MOD-GRID Skeletool Holder (Autodesk Fusion 360 design; units mm, degrees)
part number: 2026-10-25-08-48-38-444
Autodesk Fusion 360 part; units mm, degrees
ref_plane "WorkPlane52" through (-15.8, 0, 0) normal (1, 0, 0) x (0, 1, 0)
sketch "Tool section" plane through (-15.8, 0, 0) normal (1, 0, 0) x (0, 0, -1)
  arc A0 (-6, 14.25) -> (-7.5, 15.75) centre (-7.5, 14.25) ccw
  arc A1 (-17.7, 15.75) -> (-19.2, 14.25) centre (-17.7, 14.25) ccw
  arc A2 (-19.2, -14.25) -> (-17.7, -15.75) centre (-17.7, -14.25) ccw
  arc A3 (-7.5, -15.75) -> (-6, -14.25) centre (-7.5, -14.25) ccw
  line L0 (-6, 14.25) -> (-6, -14.25)
  line L1 (-7.5, 15.75) -> (-17.7, 15.75)
  line L2 (-19.2, 14.25) -> (-19.2, -14.25)
  line L3 (-7.5, -15.75) -> (-17.7, -15.75)
extrude "Extrude82" add sketch "Tool section" along normal blind 85.8 makes body 1
ref_plane "WorkPlane53" through (70, 0, 0) normal (1, 0, 0) x (0, 1, 0)
sketch "Tool end section" plane through (70, 0, 0) normal (1, 0, 0) x (0, 0, -1)
  arc A0 (-6, 12) -> (-7.5, 13.5) centre (-7.5, 12) ccw
  arc A1 (-12.5, 13.5) -> (-14, 12) centre (-12.5, 12) ccw
  arc A2 (-14, -12) -> (-12.5, -13.5) centre (-12.5, -12) ccw
  arc A3 (-7.5, -13.5) -> (-6, -12) centre (-7.5, -12) ccw
  line L0 (-6, 12) -> (-6, -12)
  line L1 (-7.5, 13.5) -> (-12.5, 13.5)
  line L2 (-14, 12) -> (-14, -12)
  line L3 (-7.5, -13.5) -> (-12.5, -13.5)
extrude "Extrude83" add sketch "Tool end section" along normal blind 15.8 bodies 1
ref_plane "WorkPlane54" through (7, 0, 0) normal (1, 0, 0) x (0, 1, 0)
sketch "Band A body" plane through (7, 0, 0) normal (1, 0, 0) x (0, 0, -1)
  line L0 (0, -23.45) -> (-22.8627, -23.45)
  line L1 (-22.8627, -23.45) -> (-22.8627, 23.45)
  line L2 (-22.8627, 23.45) -> (0, 23.45)
  line L3 (0, 23.45) -> (0, -23.45)
extrude "Extrude84" add sketch "Band A body" along normal blind 7 and the other way blind 7 separate body makes body 2
fillet "Fillet19" radius 1.5 4 edges at (7, 23.45, 0) (7, -23.45, 0) (7, -23.45, 22.8627) (7, 23.45, 22.8627) on bodies 2
sketch "Band A cavity" plane through (7, 0, 0) normal (1, 0, 0) x (0, 0, -1)
  arc A0 (-6, 16.15) -> (-6.3, 16.45) centre (-6.3, 16.15) ccw
  arc A1 (-20.8299, 15.4172) -> (-20.2642, 15.4172) centre (-20.5471, 15.7) ccw
  line L0 (-6.3, 16.45) -> (-19.2314, 16.45)
  line L1 (-19.2314, 16.45) -> (-20.2642, 15.4172)
  line L2 (-20.8299, 15.4172) -> (-21.8627, 16.45)
  line L3 (-21.8627, 16.45) -> (-24.8627, 16.45)
  arc A2 (-6.3, -16.45) -> (-6, -16.15) centre (-6.3, -16.15) ccw
  arc A3 (-20.2642, -15.4172) -> (-20.8299, -15.4172) centre (-20.5471, -15.7) ccw
  line L4 (-6.3, -16.45) -> (-19.2314, -16.45)
  line L5 (-19.2314, -16.45) -> (-20.2642, -15.4172)
  line L6 (-20.8299, -15.4172) -> (-21.8627, -16.45)
  line L7 (-21.8627, -16.45) -> (-24.8627, -16.45)
  line L8 (-6, -16.15) -> (-6, 16.15)
  line L9 (-24.8627, -16.45) -> (-24.8627, 16.45)
extrude "Extrude85" cut sketch "Band A cavity" along normal blind 14 and the other way blind 14 bodies 2
sketch "Band A relief" plane through (7, 0, 0) normal (1, 0, 0) x (0, 0, -1)
  arc A0 (-3.387, 15.0897) -> (-6.3, 19.25) centre (-6.3, 16.15) ccw
  arc A1 (-2.2593, 14.6793) -> (-6.3, 20.45) centre (-6.3, 16.15) ccw
  line L0 (-6.3, 19.25) -> (-10.3, 18.45)
  line L1 (-10.3, 18.45) -> (-24.8627, 18.45)
  line L2 (-24.8627, 18.45) -> (-24.8627, 20.45)
  line L3 (-24.8627, 20.45) -> (-6.3, 20.45)
  line L4 (-2.2593, 14.6793) -> (-3.387, 15.0897)
  circle A2 centre (-2.8231, 14.8845) radius 0.6
  arc A3 (-6.3, -19.25) -> (-3.387, -15.0897) centre (-6.3, -16.15) ccw
  arc A4 (-6.3, -20.45) -> (-2.2593, -14.6793) centre (-6.3, -16.15) ccw
  line L5 (-6.3, -19.25) -> (-10.3, -18.45)
  line L6 (-10.3, -18.45) -> (-24.8627, -18.45)
  line L7 (-24.8627, -18.45) -> (-24.8627, -20.45)
  line L8 (-24.8627, -20.45) -> (-6.3, -20.45)
  line L9 (-2.2593, -14.6793) -> (-3.387, -15.0897)
  circle A5 centre (-2.8231, -14.8845) radius 0.6
extrude "Extrude86" cut sketch "Band A relief" along normal blind 14 and the other way blind 14 bodies 2
chamfer "Chamfer19" distance 0.5 angle 45 16 edges at (0, 21.2, 22.8627) (0, 23.0107, 22.4234) (0, 23.45, 11.4314) (0, 23.0107, 0.4393) (0, 0, 0) (0, -23.0107, 0.4393) (0, -23.45, 11.4314) (0, -23.0107, 22.4234) (0, -21.2, 22.8627) (0, -17.45, 22.8627) (0, -16.45, 12.7657) (0, -16.3621, 6.0879) (0, 0, 6) (0, 16.3621, 6.0879) (0, 16.45, 12.7657) (0, 17.45, 22.8627) tangent chain off on bodies 2
ref_plane "WorkPlane55" through (0, 0, 0) normal (1, 0, 0) x (0, 1, 0)
sketch "Band A legs" plane through (0, 0, 0) normal (1, 0, 0) x (0, 0, -1)
  line L0 (-0.5, -13.45) -> (4.64, -13.45)
  line L1 (4.64, -13.45) -> (4.64, -13.93)
  line L2 (4.64, -13.93) -> (3.4, -15.19)
  line L3 (3.4, -15.19) -> (3.1, -14.32)
  line L4 (3.1, -14.32) -> (-0.5, -14.32)
  line L5 (-0.5, -14.32) -> (-0.5, -13.45)
  line L6 (-0.5, -10.55) -> (4.64, -10.55)
  line L7 (4.64, -10.55) -> (4.64, -10.07)
  line L8 (4.64, -10.07) -> (3.4, -8.81)
  line L9 (3.4, -8.81) -> (3.1, -9.68)
  line L10 (3.1, -9.68) -> (-0.5, -9.68)
  line L11 (-0.5, -9.68) -> (-0.5, -10.55)
  line L12 (-0.5, 10.55) -> (4.64, 10.55)
  line L13 (4.64, 10.55) -> (4.64, 10.07)
  line L14 (4.64, 10.07) -> (3.4, 8.81)
  line L15 (3.4, 8.81) -> (3.1, 9.68)
  line L16 (3.1, 9.68) -> (-0.5, 9.68)
  line L17 (-0.5, 9.68) -> (-0.5, 10.55)
  line L18 (-0.5, 13.45) -> (4.64, 13.45)
  line L19 (4.64, 13.45) -> (4.64, 13.93)
  line L20 (4.64, 13.93) -> (3.4, 15.19)
  line L21 (3.4, 15.19) -> (3.1, 14.32)
  line L22 (3.1, 14.32) -> (-0.5, 14.32)
  line L23 (-0.5, 14.32) -> (-0.5, 13.45)
extrude "Extrude87" add sketch "Band A legs" along normal blind 4.76 bodies 2
ref_plane "WorkPlane56" through (80.4, 0, 0) normal (1, 0, 0) x (0, 1, 0)
sketch "Pocket body" plane through (80.4, 0, 0) normal (1, 0, 0) x (0, 0, -1)
  line L0 (0, -23.45) -> (-16.07, -23.45)
  line L1 (-16.07, -23.45) -> (-16.07, 23.45)
  line L2 (-16.07, 23.45) -> (0, 23.45)
  line L3 (0, 23.45) -> (0, -23.45)
extrude "Extrude88" add sketch "Pocket body" along normal blind 8.4 and the other way blind 8.4 separate body makes body 3
fillet "Fillet20" radius 1.5 4 edges at (80.4, 23.45, 0) (80.4, -23.45, 0) (80.4, -23.45, 16.07) (80.4, 23.45, 16.07) on bodies 3
ref_plane "WorkPlane57" through (72, 0, 0) normal (1, 0, 0) x (0, 1, 0)
sketch "Pocket cavity" plane through (72, 0, 0) normal (1, 0, 0) x (0, 0, -1)
  arc A0 (-5.83, 13.57) -> (-6.13, 13.87) centre (-6.13, 13.57) ccw
  arc A1 (-14.27, 13.87) -> (-14.57, 13.57) centre (-14.27, 13.57) ccw
  arc A2 (-14.57, -13.57) -> (-14.27, -13.87) centre (-14.27, -13.57) ccw
  arc A3 (-6.13, -13.87) -> (-5.83, -13.57) centre (-6.13, -13.57) ccw
  line L0 (-5.83, 13.57) -> (-5.83, -13.57)
  line L1 (-6.13, 13.87) -> (-14.27, 13.87)
  line L2 (-14.57, 13.57) -> (-14.57, -13.57)
  line L3 (-6.13, -13.87) -> (-14.27, -13.87)
extrude "Extrude89" cut sketch "Pocket cavity" along normal blind 14.3 and the other way blind 14.3 bodies 3
chamfer "Chamfer20" distance 0.5 angle 45 16 edges at (72, 0, 5.83) (72, 13.7821, 5.9179) (72, 13.87, 10.2) (72, 13.7821, 14.4821) (72, 0, 14.57) (72, -13.7821, 14.4821) (72, -13.87, 10.2) (72, -13.7821, 5.9179) (72, 23.0107, 15.6307) (72, 0, 16.07) (72, -23.0107, 15.6307) (72, -23.45, 8.035) (72, -23.0107, 0.4393) (72, 0, 0) (72, 23.0107, 0.4393) (72, 23.45, 8.035) tangent chain off on bodies 3
ref_plane "WorkPlane58" through (72, 0, 0) normal (1, 0, 0) x (0, 1, 0)
sketch "Tip Pocket legs" plane through (72, 0, 0) normal (1, 0, 0) x (0, 0, -1)
  line L0 (-0.5, -13.45) -> (4.64, -13.45)
  line L1 (4.64, -13.45) -> (4.64, -13.93)
  line L2 (4.64, -13.93) -> (3.4, -15.19)
  line L3 (3.4, -15.19) -> (3.1, -14.32)
  line L4 (3.1, -14.32) -> (-0.5, -14.32)
  line L5 (-0.5, -14.32) -> (-0.5, -13.45)
  line L6 (-0.5, -10.55) -> (4.64, -10.55)
  line L7 (4.64, -10.55) -> (4.64, -10.07)
  line L8 (4.64, -10.07) -> (3.4, -8.81)
  line L9 (3.4, -8.81) -> (3.1, -9.68)
  line L10 (3.1, -9.68) -> (-0.5, -9.68)
  line L11 (-0.5, -9.68) -> (-0.5, -10.55)
  line L12 (-0.5, 10.55) -> (4.64, 10.55)
  line L13 (4.64, 10.55) -> (4.64, 10.07)
  line L14 (4.64, 10.07) -> (3.4, 8.81)
  line L15 (3.4, 8.81) -> (3.1, 9.68)
  line L16 (3.1, 9.68) -> (-0.5, 9.68)
  line L17 (-0.5, 9.68) -> (-0.5, 10.55)
  line L18 (-0.5, 13.45) -> (4.64, 13.45)
  line L19 (4.64, 13.45) -> (4.64, 13.93)
  line L20 (4.64, 13.93) -> (3.4, 15.19)
  line L21 (3.4, 15.19) -> (3.1, 14.32)
  line L22 (3.1, 14.32) -> (-0.5, 14.32)
  line L23 (-0.5, 14.32) -> (-0.5, 13.45)
extrude "Extrude90" add sketch "Tip Pocket legs" along normal blind 4.76 bodies 3
equation "tool_w = 31.50 mm" comment "OFFICIAL LEATHERMAN SPEC, closed (1.24 in). Across the handles - the direction that lies flat on the plate. NOT yet caliper-checked on the actual tool."
equation "tool_t = 13.20 mm" comment "OFFICIAL LEATHERMAN SPEC, closed overall thickness (0.52 in). This is the dimension the bands reach over. The multitool.org wiki says 16 mm, which is almost certainly WITH the removable pocket clip fitted - see the notes at the top of this file."
equation "tool_len = 101.60 mm" comment "OFFICIAL LEATHERMAN SPEC, closed length (4.00 in). Only sets where the reference body ends and how far apart the bands can sit."
equation "tool_r = 1.50 mm" comment "ESTIMATE of the cross-section corner radius. Unlike the Skeletool, NOTHING IN THIS DESIGN DEPENDS ON IT: the cavity is squarer than any plausible value and the bead sits entirely ABOVE the tool's top face, so it overhangs the flat rather than grazing the corner. It only shapes the reference body. run() sweeps 0..4 to prove the insensitivity rather than assert it."
equation "cav_clear = 1.40 mm" comment "Clearance on the cavity width (total)"
equation "cav_hw = ( tool_w + cav_clear ) / 2" comment "Cavity half width"
equation "cav_r = 0.30 mm" comment "Cavity bottom corner radius. SQUARER than the tool on purpose: a cavity corner rounder than the tool is what jammed every previous version. Also the arc the relief slot follows."
equation "base_t = 6.00 mm" comment "Base under the tool. It sets how far the slot root sits above the z=0 face (base_t + cav_r - r_out, want >= 1.5); it does NOT set the root web, which is base_t-independent because the cavity floor and the slot rise together."
equation "arm_root = 2.80 mm" comment "Arm thickness AT THE ROOT = 7 extrusions at 0.4. The arm is TAPERED, thick at the base and thinner at the tip, because the bending moment is largest at the root and nearly zero at the bead. A thick root also pushes the relief slot further out, which is what gives the root web its thickness - see root_web()."
equation "arm_tip = 2.00 mm" comment "Arm thickness at the bead = 5 extrusions. Keep every flexure wall an integer multiple of the extrusion width and >= 4 of them: 1.2 mm is 2.86 extrusions, so the slicer lays a gap-fill bond line down the middle of the flexure."
equation "arm_blend = 4.00 mm" comment "Height above the cavity corner over which arm_root blends down to arm_tip. A step here would be a stress riser; blending over several mm keeps the thick material where the moment is and still leaves most of the arm compliant."
equation "relief_w = 1.20 mm" comment "Relief slot width behind the arm"
equation "relief_a0 = -110 deg" comment "Relief slot root angle about the cavity corner centre. Past -90 it tucks under the floor and buys arm length, but it also EATS THE ROOT WEB: past -90 the nearest cavity surface is the floor, not the corner arc, so the web stops being arm_root and starts shrinking fast. -135 left only 0.52 mm, which the bed chamfer then cut to 0.016. run() computes it."
equation "rail_t = 3.00 mm" comment "Outer rail beyond the relief slot. With body_corner_r it sets the top land between slot and fillet: keep that > 2 * first_layer_cham."
equation "bead_clear = 0.10 mm" comment "Gap between the BOTTOM of the bead and the tool's top face when seated. Also the lift play before the bead bites."
equation "lip_over = 0.45 mm" comment "How far each bead reaches inboard of the tool's side face - and therefore the splay each arm takes. This IS the deflection, and deflection sets the bending stress, so it is budgeted against SIG_LIMIT rather than maximised. Thinning an arm to buy more reach is exactly the mistake that produced a 0.016 mm root web on the Skeletool band."
equation "bead_r = lip_over + cav_clear / 2" comment "Bead radius. Half circle tangent to the cavity wall above and below, so the arm's inner face is one continuous curve with no tooth to snap off."
equation "bead_z = base_t + tool_t + bead_clear + bead_r" comment "Bead centre height, placed so the bead's LOWEST point sits bead_clear above the tool's top face. The whole bead is therefore above the top face and overhangs the FLAT, never the corner - which is why tool_r drops out of the design. It also lengthens the arm by a bead radius over the Skeletool's corner-tangent rule, which is worth about 1 MPa."
equation "lip_tip_y = tool_w / 2 - lip_over" comment "Innermost point of the bead"
equation "land_h = 1.00 mm" comment "Band height above the bead"
equation "band_len = 14.0 mm" comment "Band width along the tool = part height when printed. Grip force scales with band length and peak stress does NOT, so length is the one free way to buy retention."
equation "band_hw = cav_hw + arm_root + relief_w + rail_t" comment "Band half width - set by the ROOT thickness, which is the widest part of the arm"
equation "band_h = lip_z0 + 2 * lip_proj + land_h" comment "Band overall height"
equation "band_a_x = 0 mm" comment "Band A bed face"
equation "band_cells = 7" comment "Grid cells between the two bands = 56 mm. Keeps both bands on the straight part of the handle, clear of the plier head at one end and the carabiner at the other."
equation "grid_pitch = 8 mm" comment "MOD-GRID pitch"
equation "band_b_x = band_a_x + band_cells * grid_pitch" comment "Band B bed face"
equation "body_corner_r = 1.50 mm" comment "Rounded outer corners"
equation "first_layer_cham = 0.50 mm" comment "Elephant-foot chamfer on the bed face"
equation "leg_pair_y = 12.0 mm" comment "Leg pairs at +/- this; 24 mm apart = 3 cells"
equation "leg_clear = 0.14 mm" comment "Shrinks the leg LENGTH and SHANK (not the barb). MEASURED: this printer runs 0.07 per wall."
equation "leg_hole_len = 4.90 mm - leg_clear" comment "Leg extent along the print axis"
equation "leg_inner_hw = 1.45 mm" comment "Leg inner face from pair centre -> 2.90 gap"
equation "leg_shank_hw = 2.39 mm - leg_clear / 2" comment "Relaxed shank half-span"
equation "barb_hw = 3.19 mm" comment "Barb peak half-span - NOT reduced, it is meant to squeeze"
equation "barb_z = -3.40 mm" comment "Barb peak depth below the seating face"
equation "catch_z = -3.10 mm" comment "Catch face: 0.10 below the 3.00 plate"
equation "leg_tip_z = -4.64 mm" comment "Leg tip"
equation "leg_tip_hw = 2.00 mm - leg_clear / 2" comment "Tip half-span, sets the ~45 deg lead-in"
equation "tool_r_min = 0.20 mm" comment "The SQUAREST corner the handle could plausibly have. The capture lip is placed so it still clears THIS at seated, which is the recoverable bias: a squarer tool can never be held proud, a rounder one only lifts further before the lip bites."
equation "lip_clear = 0.60 mm" comment "Gap between the lip's underside and the tool's top corner when seated, evaluated at tool_r_min. The arms are UNLOADED when the tool is home, so there is no creep."
equation "lip_tipr = 0.40 mm" comment "Radius on the lip tip = ONE NOZZLE WIDTH. A knife edge will not print. It also confines the only part of the stroke where the contact normal can reach horizontal - see seat_check(); a round bead lets that happen over ~0.5 mm and the Zippo band printed with one held the lighter 2 mm proud."
equation "lip_apex_y = lip_tip_y - 0.4142135624 * lip_tipr" comment "Virtual apex where the two 45 deg faces would meet if the tip were not rounded"
equation "lip_proj = cav_hw - lip_apex_y" comment "How far the apex stands proud of the cavity wall. At 45 deg this is also the RISE of each face, so the lip is 2 * lip_proj tall."
equation "lip_z0 = 1.4142135624 * ( tool_r_min + lip_clear ) + tool_w / 2 + base_t + tool_t - 2 * tool_r_min - cav_hw" comment "Foot of the capture ramp, where the 45 deg underside leaves the cavity wall. Derived, not chosen: the underside is the line y + z = cav_hw + lip_z0, and this is the lowest it can sit while still standing lip_clear off a tool corner of radius tool_r_min."
equation "lip_zt = lip_z0 + lip_proj" comment "Height of the lip tip = where the load is applied to the arm"
equation "tool_overhang = 15.80 mm" comment "How much tool stands proud of Band A's bed face. Frozen at the value the old two-band layout produced - (band_a_x + band_b_x + band_len - tool_len) / 2 with Band B at 7 cells - so that BAND A STILL GRIPS EXACTLY THE SAME PART OF THE HANDLE as the version Rob has printed and likes. Do not \"tidy\" this to zero without re-checking what the band lands on."
equation "tool_x0 = band_a_x - tool_overhang" comment "Tool's near end"
equation "print_bias = 0.07 mm" comment "MEASURED on this printer: a cavity comes out 0.07 per wall UNDER nominal. The pocket is modelled oversize by this so the INTERNAL DIMENSIONS PRINT AT THE NUMBERS ROB ASKED FOR, rather than 0.14 under them."
equation "pocket_id_w = 27.60 mm" comment "Pocket internal WIDTH as it should measure ON THE PRINTED PART. The cut is modelled 2 * print_bias wider than this."
equation "pocket_id_h = 8.60 mm" comment "Pocket internal HEIGHT as it should measure ON THE PRINTED PART."
equation "pocket_cells = 9" comment "Grid cells from Band A to the pocket mouth = 72 mm, which puts the mouth 13.8 mm short of the tool's far end so that much of the tool is captured."
equation "pocket_x0 = band_a_x + pocket_cells * grid_pitch" comment "Pocket MOUTH = its bed face. The legs are flush with this, and it faces Band A."
equation "pocket_floor_clear = 0.10 mm" comment "How far the pocket floor sits below the band's cavity floor, so the tool is carried by the band and does not rock on three points."
equation "pocket_z0 = base_t - pocket_floor_clear - print_bias" comment "Pocket floor, modelled. Prints at base_t - pocket_floor_clear."
equation "pocket_z1 = pocket_z0 + pocket_id_h + 2 * print_bias" comment "Pocket ceiling, modelled"
equation "pocket_hw = pocket_id_w / 2 + print_bias" comment "Pocket half width, modelled"
equation "pocket_r = 0.30 mm" comment "Pocket corner radius. SQUARER than any plausible tool edge, same reasoning and same value as cav_r: a cavity corner ROUNDER than the part lands on the part's corners and holds it off, which is what jammed three Zippo versions."
equation "tip_gap = 0.50 mm" comment "Air between the tool's end and the blind face. This is the axial stop that positions the tool."
equation "pocket_depth = tool_x0 + tool_len + tip_gap - pocket_x0" comment "Cavity depth, derived so the blind face lands tip_gap past the tool's end."
equation "pocket_end_t = 2.50 mm" comment "Material capping the blind end. Printed standing on the mouth this is a ceiling over the cavity, and the slicer bridges its SHORT span - pocket_id_h, 10 mm - not the 30 mm one, so it is within this project's own bridge limit."
equation "pocket_roof = 1.50 mm" comment "Material above the cavity"
equation "pocket_len = pocket_depth + pocket_end_t" comment "Pocket overall length"
equation "pocket_h = pocket_z1 + pocket_roof" comment "Pocket overall height"
equation "pocket_body_hw = band_hw" comment "Same half width as the band so the two bodies look like a set"
equation "pocket_fit_clear = 0.50 mm" comment "ASSUMED clearance between the pocket ID and the tool's end section. Rob gave the POCKET ID (30 x 10), not the tool, so the reference body's end is built this much under it purely so the interference check has real geometry to work against. If the end section is ever measured, set tool_end_w/tool_end_t directly and delete this."
equation "tool_end_w = 27.00 mm" comment "ASSUMED width of the tool's far end - see pocket_fit_clear"
equation "tool_end_t = 8.00 mm" comment "ASSUMED thickness of the tool's far end. Its UNDERSIDE is taken as flush with the rest of the handle, the way the tool lies on the plate."
equation "tool_step_x = pocket_x0 - 2.0 mm" comment "Where the reference body steps down to the end section - just outside the pocket mouth, so the step itself is never inside the pocket."
equation "d490 = tool_x0"
equation "d492 = tool_step_x - tool_x0"
equation "d494 = tool_step_x"
equation "d496 = tool_x0 + tool_len - tool_step_x"
equation "d498 = band_a_x + band_len / 2"
equation "d500 = band_len / 2"
equation "d502 = band_len / 2"
equation "d505 = body_corner_r"
equation "d506 = band_len"
equation "d508 = band_len"
equation "d510 = band_len"
equation "d512 = band_len"
equation "d514 = first_layer_cham"
equation "d515 = band_a_x"
equation "d517 = leg_hole_len"
equation "d519 = pocket_x0 + pocket_len / 2"
equation "d521 = pocket_len / 2"
equation "d523 = pocket_len / 2"
equation "d526 = body_corner_r"
equation "d527 = pocket_x0"
equation "d529 = pocket_depth"
equation "d531 = pocket_depth"
equation "d533 = first_layer_cham"
equation "d534 = pocket_x0"
equation "d536 = leg_hole_len"
named bodies: "Reference - Skeletool", "Band A", "Tip Pocket"
